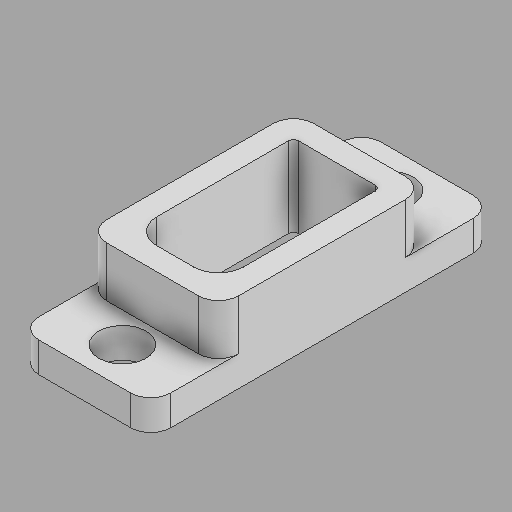
# Autodesk Inventor part: XT60_M_mount
Saved by Autodesk Inventor 2025 (Build 290162000, 162)
## iProperties
Created: 2024-11-14
Part Number: XT60_M_mount
Material: 일반
Document SubType Name: Modeling
Designer: OSB
Density: 1 g/cm^3
Appearance: 기본값
Author: OSB
Autodesk Inventor part; units mm, degrees
ref_plane "YZ Plane" through (0, 0, 0) normal (1, 0, 0) x (0, 1, 0)
ref_plane "XZ Plane" through (0, 0, 0) normal (0, 1, 0) x (-1, 0, 0)
ref_plane "XY Plane" through (0, 0, 0) normal (0, 0, 1) x (1, 0, 0)
sketch "스케치1" plane through (0, 0, 0) normal (0, 0, 1) x (1, 0, 0)
  line L0 (-8.3, -4.57) -> (8.3, -4.57)
  line L1 (8.3, -4.57) -> (8.3, 4.57)
  line L2 (8.3, 4.57) -> (-8.3, 4.57)
  line L3 (-8.3, 4.57) -> (-8.3, -4.57)
  line L4 (-8.3, -4.57) -> (8.3, 4.57) construction
  line L5 (8.3, -4.57) -> (-8.3, 4.57) construction
  circle A0 centre (-13.3, 0) radius 2.35
  line L6 (-10.3, 6.57) -> (10.3, 6.57)
  line L7 (10.3, 6.57) -> (10.3, -6.57)
  line L8 (10.3, -6.57) -> (-10.3, -6.57)
  line L9 (-10.3, -6.57) -> (-10.3, 6.57)
  line L10 (-13.3, 3.1754) -> (-10.55, 1.5877)
  line L11 (-10.55, 1.5877) -> (-10.55, -1.5877)
  line L12 (-10.55, -1.5877) -> (-13.3, -3.1754)
  line L13 (-13.3, -3.1754) -> (-16.05, -1.5877)
  line L14 (-16.05, -1.5877) -> (-16.05, 1.5877)
  line L15 (-16.05, 1.5877) -> (-13.3, 3.1754)
  line L16 (0, 4.57) -> (0, -4.57) construction
  line L17 (-10.3, 6.57) -> (-17.05, 6.57)
  line L18 (-17.05, 6.57) -> (-17.05, -6.57)
  line L19 (-17.05, -6.57) -> (-10.3, -6.57)
  line L20 (-10.3, -6.57) -> (-10.3, 6.57)
  circle A1 centre (13.3, 0) radius 2.35
  line L21 (13.3, 3.1754) -> (10.55, 1.5877)
  line L22 (10.55, 1.5877) -> (10.55, -1.5877)
  line L23 (10.55, -1.5877) -> (13.3, -3.1754)
  line L24 (13.3, -3.1754) -> (16.05, -1.5877)
  line L25 (16.05, -1.5877) -> (16.05, 1.5877)
  line L26 (16.05, 1.5877) -> (13.3, 3.1754)
  line L27 (10.3, 6.57) -> (17.05, 6.57)
  line L28 (17.05, 6.57) -> (17.05, -6.57)
  line L29 (17.05, -6.57) -> (10.3, -6.57)
  line L30 (-8.05, 4.32) -> (8.05, 4.32)
  line L31 (8.05, 4.32) -> (8.05, -4.32)
  line L32 (8.05, -4.32) -> (-8.05, -4.32)
  line L33 (-8.05, -4.32) -> (-8.05, 4.32)
  point P0 (0, 0)
  dimension "d0" = 16.6
  dimension "d1" = 9.14
  dimension "d2" = 4.7
  dimension "d4" = 2
  dimension "d7" = 5.5
  dimension "d8" = 3
  dimension "d19" = 1
  dimension "d20" = 0.25
  constraints: 68 end point, 10 symmetric about line, 8 parallel, 4 midpoint, 4 perpendicular, 2 centre point, 2 coincident, 2 horizontal, 1 horizontal alignment, 1 vertical alignment, 20 other
  measures "d0" distance of L2.end L1.end
  measures "d1" distance of L1.end L0.end
  measures "d2" diameter of A0
  measures "d4" distance between parallel lines of L2 L6
  measures "d7" distance between parallel lines of L14 L11
  measures "d8" distance from line of A0.centre L9
  measures "d19" distance between parallel lines of L18 L14
  measures "d20" distance between parallel lines of L2 L30
extrude "돌출1" add sketch "스케치1" along normal blind 8 contours L3 L2 L1 L0 | L6 L7 L8 L9
extrude "돌출2" add sketch "스케치1" along normal blind 3 contours L9 L19 L18 L17 | L27 L28 L29 L7 | L10 L11 L12 L13 L14 L15 | L26 L25 L24 L23 L22 L21
extrude "돌출3" [suppressed]
fillet "모깎기1" radius 2 8 edges at (17.05, 6.57, 1.5) (17.05, -6.57, 1.5) (-17.05, 6.57, 1.5) (-17.05, -6.57, 1.5) (10.3, 6.57, 5.5) (10.3, -6.57, 5.5) (-10.3, -6.57, 5.5) (-10.3, 6.57, 5.5)
fillet "모깎기2" radius 2.5 2 edges at (8.05, -4.32, 4) (8.05, 4.32, 4)
fillet "모깎기3" radius 0.5 2 edges at (-8.05, -4.32, 4) (-8.05, 4.32, 4)
